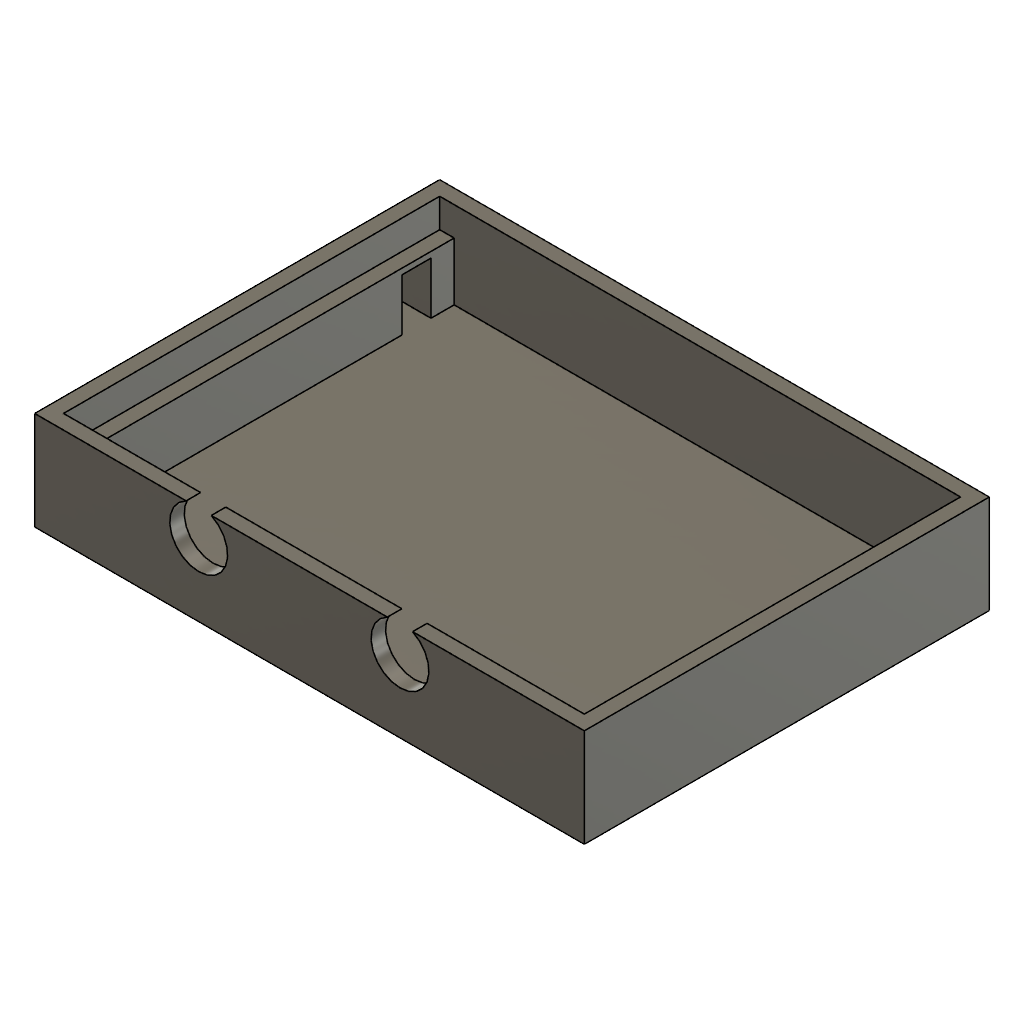
Theremin Casing (Autodesk Fusion 360 design; units mm, degrees)
part number: 2026-10-26-04-25-07-203
Autodesk Fusion 360 part; units mm, degrees
sketch "Sketch1" plane through (0, 0, 0) normal (0, 1, 0) x (1, 0, 0)
  line L0 (0, 0) -> (95, 0)
  line L1 (95, 0) -> (95, 70)
  line L2 (95, 70) -> (0, 70)
  line L3 (0, 70) -> (0, 0)
  line L4 (1.5, 1.5) -> (93.5, 1.5)
  line L5 (93.5, 1.5) -> (93.5, 68.5)
  line L6 (93.5, 68.5) -> (1.5, 68.5)
  line L7 (1.5, 68.5) -> (1.5, 1.5)
  dimension "d1" = 95
  dimension "d2" = 70
  dimension "d3" = -1.5
  constraint horizontal L0
  constraint vertical L1
  constraint horizontal L2
  constraint vertical L3
  constraint coincident L0.start L3.end
  measures "d1" distance of L0.start L0.end
  measures "d2" distance of L0.start L2.end
extrude "Extrude1" add sketch "Sketch1" along normal blind 2 contours L0 L1 L2 L3 | L4 L5 L6 L7
sketch "Sketch2" plane through (0, 2, 0) normal (0, 1, 0) x (-1, 0, 0)
  line L0 (0, -70) -> (0, 0)
  line L1 (0, 0) -> (-95, 0)
  line L2 (-95, 0) -> (-95, -70)
  line L3 (-95, -70) -> (0, -70)
  line L4 (-2.5, -2.5) -> (-92.5, -2.5)
  line L5 (-92.5, -2.5) -> (-92.5, -67.5)
  line L6 (-92.5, -67.5) -> (-2.5, -67.5)
  line L7 (-2.5, -67.5) -> (-2.5, -2.5)
  dimension "d6" = -2.5
extrude "Extrude2" add sketch "Sketch2" along normal blind 15
sketch "Sketch4" plane through (0, 2, 0) normal (0, 1, 0) x (-1, 0, 0)
  line L0 (-2.5, -2.5) -> (-92.5, -2.5)
  line L1 (-92.5, -2.5) -> (-92.5, -67.5)
  line L2 (-92.5, -67.5) -> (-2.5, -67.5)
  line L3 (-2.5, -67.5) -> (-2.5, -2.5)
  line L4 (-92.5, -2.5) -> (-90, -2.5)
  line L5 (-90, -2.5) -> (-90, -67.5)
  line L6 (-90, -67.5) -> (-92.5, -67.5)
  line L7 (-92.5, -67.5) -> (-92.5, -2.5)
  line L8 (-2.5, -2.5) -> (-5, -2.5)
  line L9 (-5, -2.5) -> (-5, -67.5)
  line L10 (-5, -67.5) -> (-2.5, -67.5)
  line L11 (-2.5, -67.5) -> (-2.5, -2.5)
  dimension "d13" = 2.5
  dimension "d14" = 2.5
  dimension "d15" = 65
  constraint horizontal L4
  constraint vertical L5
  constraint horizontal L6
  constraint vertical L7
  constraint coincident L0.end L1.start
  constraint horizontal L8
  constraint vertical L9
  constraint horizontal L10
  constraint vertical L11
  constraint coincident L0.start L3.end
  measures "d13" distance of L0.end L4.end
  measures "d14" distance of L0.start L8.end
  measures "d15" distance of L0.start L2.end
extrude "Extrude4" add sketch "Sketch4" along normal blind 10 contours L0 L2 L3 L8 L9 L10 L11 | L0 L1 L2 L4 L5 L6 L7
sketch "Sketch5" plane through (0, 0, 0) normal (0, 0, 1) x (1, 0, 0)
  line L0 (0, 0) -> (95, 0)
  line L1 (95, 0) -> (95, 17)
  line L2 (95, 17) -> (0, 17)
  line L3 (0, 17) -> (0, 0)
  line L4 (90, 17) -> (90, 0) construction
  line L5 (70, 0) -> (56.2891, 0) construction
  line L6 (21.5, 0) -> (21.5, 14.4271) construction
  circle A0 centre (28.3555, 12.5) radius 5
  line L7 (35.2109, 12.5) -> (21.5, 12.5) construction
  line L8 (28.3555, 0) -> (28.3555, 14.4271) construction
  line L9 (35.2109, 0) -> (21.5, 0) construction
  line L10 (21.5, 14.4271) -> (35.2109, 14.4271) construction
  line L11 (35.2109, 14.4271) -> (35.2109, 0) construction
  line L12 (56.2891, 0) -> (56.2891, 15) construction
  line L13 (56.2891, 15) -> (70, 15) construction
  line L14 (70, 15) -> (70, 0) construction
  line L15 (56.2891, 12.5) -> (70, 12.5) construction
  line L16 (63.1445, 15) -> (63.1445, 0) construction
  circle A1 centre (63.1445, 12.5) radius 5
  dimension "d18" = 5
  dimension "d19" = 20
  dimension "d23" = 10
  dimension "d24" = 21.5
  dimension "d31" = 15
  dimension "d32" = 12.5
  dimension "d33" = 10
  constraint coincident L0 L4.end
  constraint perpendicular L0 L4
  constraint horizontal L5
  constraint coincident L0 L5.start
  constraint horizontal L9
  constraint vertical L6
  constraint horizontal L10
  constraint vertical L11
  constraint coincident L7.start L11
  constraint coincident L7.end L6
  constraint perpendicular L6 L7
  constraint midpoint L8.start L9
  constraint midpoint L8.end L10
  constraint midpoint A0.centre L7
  constraint perpendicular L5 L12
  constraint perpendicular L12 L13
  constraint perpendicular L5 L14
  constraint coincident L12 L15.start
  constraint coincident L14 L15.end
  constraint perpendicular L14 L15
  constraint midpoint L13 L16.start
  constraint midpoint L5 L16.end
  constraint midpoint L15 A1.centre
  measures "d18" distance of L0.end L4.end
  measures "d19" distance of L4.end L5.start
  measures "d23" diameter of A0
  measures "d24" distance of L0.start L6.start
  measures "d31" distance of L5.end L12.end
  measures "d32" distance of L5.start L15.end
  measures "d33" diameter of A1
extrude "Extrude5" cut sketch "Sketch5" against normal blind 9 contours L2 A0 | L2 A1 picked at (29.4101, 14.3531) picked at (61.4279, 12.4337)
sketch "Sketch6" plane through (0, 0, 0) normal (-1, 0, 0) x (0, 0, 1)
  line L0 (-70, 0) -> (0, 0)
  line L1 (0, 17) -> (-70, 17)
  line L2 (-70, 17) -> (-70, 0)
  line L3 (-63.5, 2) -> (-58.5, 2)
  line L4 (-58.5, 2) -> (-58.5, 11)
  line L5 (-58.5, 11) -> (-63.5, 11)
  line L6 (-63.5, 11) -> (-63.5, 2)
  line L7 (0, 0) -> (0, 17)
  dimension "d27" = 6.5
  dimension "d28" = 2
  constraint horizontal L3
  constraint vertical L4
  constraint horizontal L5
  constraint vertical L6
  measures "d27" distance of L2 L3.start
  measures "d28" distance of L0 L3
extrude "Extrude6" cut sketch "Sketch6" against normal blind 8 contours L3 L4 L5 L6
